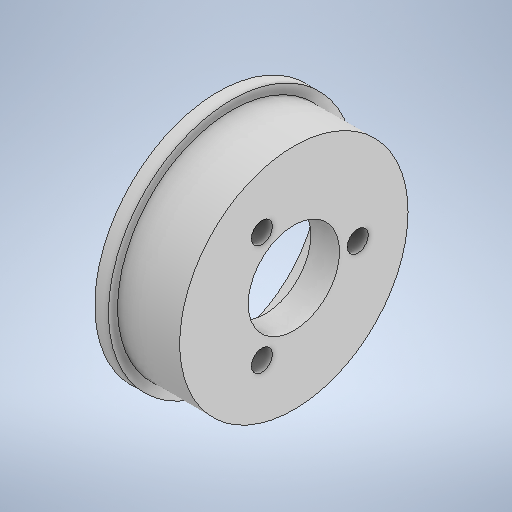
# Autodesk Inventor part: koszyczek silnikowy
Saved by Autodesk Inventor 2025.2 (Build 292293000, 293)
## iProperties
Created: 2025-04-07
Part Number: koszyczek silnikowy
Material: Ogólny
Document SubType Name: Modeling
Designer: Jan Bołtralik
Density: 1 g/cm^3
Appearance: Domyślna
Author: Jan Bołtralik
Autodesk Inventor part; units mm, degrees
ref_plane "YZ Plane" through (0, 0, 0) normal (1, 0, 0) x (0, 1, 0)
ref_plane "XZ Plane" through (0, 0, 0) normal (0, 1, 0) x (-1, 0, 0)
ref_plane "XY Plane" through (0, 0, 0) normal (0, 0, 1) x (1, 0, 0)
sketch "Szkic1" plane through (0, 0, 0) normal (0, 1, 0) x (-1, 0, 0)
  line L0 (0, 4) -> (11, 4)
  line L1 (0, -1) -> (3.15, -1)
  line L2 (3.15, -1) -> (3.15, -7)
  line L3 (3.15, -7) -> (8.3, -7)
  line L4 (8.3, -7) -> (8.3, -9.5)
  line L5 (8.3, -9.5) -> (6.8, -9.5)
  line L6 (6.8, -9.5) -> (6.8, -8.5)
  line L7 (6.8, -8.5) -> (0, -8.5)
  line L8 (0, -8.5) -> (0, -1)
  dimension "d0" = 11
  dimension "d5" = 3.15
  dimension "d6" = 5.15
  dimension "d8" = 1.5
  dimension "d10" = 22
  dimension "d11" = 25
  dimension "d12" = 10
  dimension "d13" = 27
  constraints: 18 end point, 5 perpendicular, 3 horizontal, 1 parallel
  measures "d0" distance of L0.start L0.end
  measures "d5" distance of L1.start L1.end
  measures "d6" distance of L2.end L3.end
  measures "d8" distance of L4.end L5.end
  measures "d10" diameter of L3 L0
  measures "d11" diameter of L7 L0
  measures "d12" diameter of L1 L0
  measures "d13" diameter of L5 L0
revolve "Obrót1" add sketch "Szkic1" angle 360 about axis through (0, 0, 4) along (-1, 0, 0)
sketch "Szkic2" plane through (0, 0, 4) normal (1, 0, 0) x (0, 0, -1)
  circle A0 centre (0, 0) radius 12.5 projected
  circle A1 centre (0, 0) radius 5 projected
  circle A2 centre (0, 0) radius 7
  point P0 (7, 0)
  dimension "d15" = 14
  constraints: 1 coincident, 1 horizontal alignment, 2 other
hole "Otwór1" at (0, 0, -3) direction (-1, 0, 0) diameter 2.3 depth 10 tip angle 118 clearance for "Countersunk Flat Head Screw ISO 2009/7046" size "M2" standard "ISO"
pattern_circular "Szyk kołowy1" count 3 over 360 about axis through (-3.4, 0, 4) along (-1, 0, 0) of "Otwór1"
